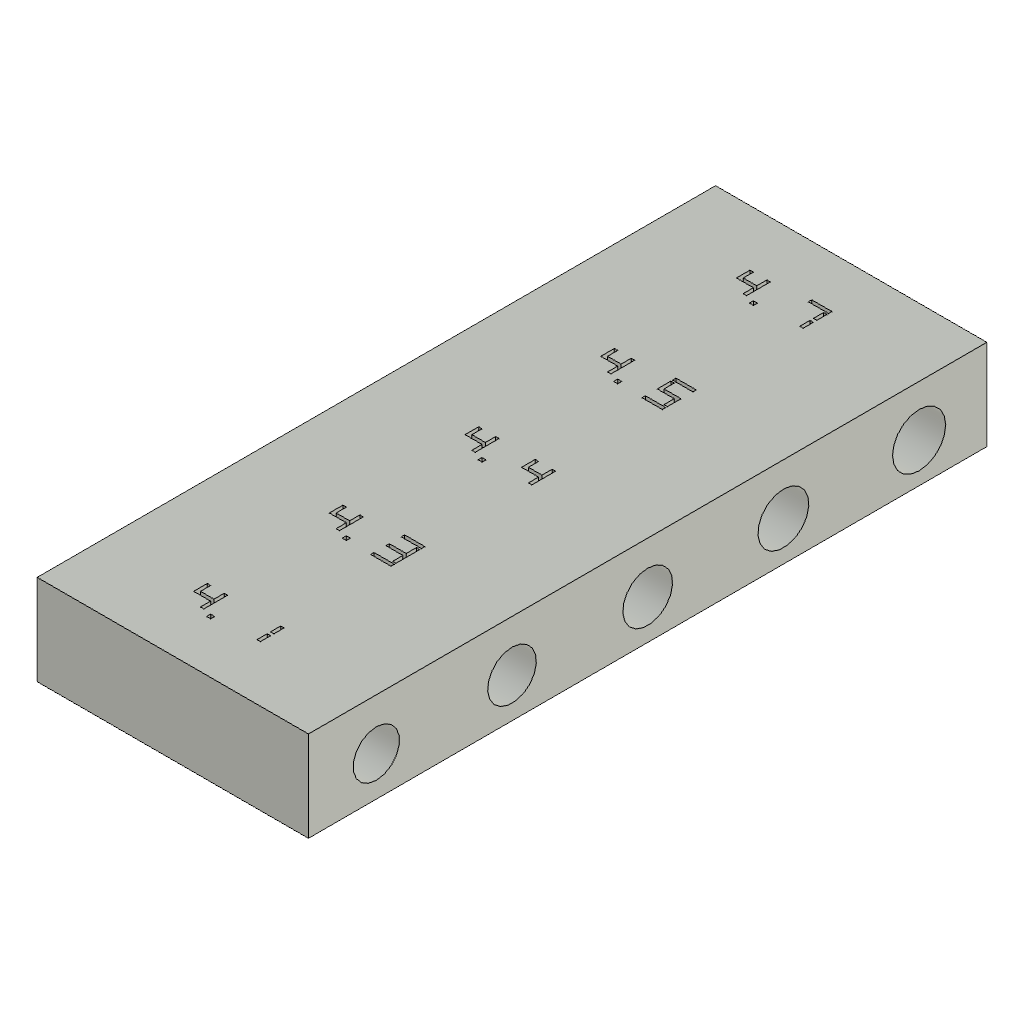
spar_fit_coupon (Autodesk Fusion 360 design; units mm, degrees)
part number: 2026-10-10-16-37-40-339
Autodesk Fusion 360 part; units mm, degrees
sketch "Fit block sketch" plane through (0, 0, 0) normal (0, 0, 1) x (1, 0, 0)
  line L0 (0, 0) -> (24, 0)
  line L1 (24, 0) -> (24, 60)
  line L2 (24, 60) -> (0, 60)
  line L3 (0, 60) -> (0, 0)
extrude "Fit block" add sketch "Fit block sketch" along normal blind 8
ref_plane "WorkPlane1" through (-0.05, 0, 0) normal (1, 0, 0) x (0, 1, 0)
sketch "Horizontal 4.1 mm fit bore sketch" plane through (-0.05, 0, 0) normal (1, 0, 0) x (0, 0, -1)
  circle A0 centre (-3.5, 6) radius 2.05
extrude "Horizontal 4.1 mm fit bore" cut sketch "Horizontal 4.1 mm fit bore sketch" along normal blind 24.1
ref_plane "WorkPlane2" through (0, 0, 7.4) normal (0, 0, 1) x (1, 0, 0)
sketch "Label 4.1 digit 0 f sketch" plane through (0, 0, 7.4) normal (0, 0, 1) x (1, 0, 0)
  line L0 (8, 6.15) -> (8.3, 6.15)
  line L1 (8.3, 6.15) -> (8.3, 7.05)
  line L2 (8.3, 7.05) -> (8, 7.05)
  line L3 (8, 7.05) -> (8, 6.15)
extrude "Label 4.1 digit 0 f" cut sketch "Label 4.1 digit 0 f sketch" along normal blind 1
ref_plane "WorkPlane3" through (0, 0, 7.4) normal (0, 0, 1) x (1, 0, 0)
sketch "Label 4.1 digit 0 g sketch" plane through (0, 0, 7.4) normal (0, 0, 1) x (1, 0, 0)
  line L0 (8, 5.85) -> (9.8, 5.85)
  line L1 (9.8, 5.85) -> (9.8, 6.15)
  line L2 (9.8, 6.15) -> (8, 6.15)
  line L3 (8, 6.15) -> (8, 5.85)
extrude "Label 4.1 digit 0 g" cut sketch "Label 4.1 digit 0 g sketch" along normal blind 1
ref_plane "WorkPlane4" through (0, 0, 7.4) normal (0, 0, 1) x (1, 0, 0)
sketch "Label 4.1 digit 0 b sketch" plane through (0, 0, 7.4) normal (0, 0, 1) x (1, 0, 0)
  line L0 (9.5, 6.15) -> (9.8, 6.15)
  line L1 (9.8, 6.15) -> (9.8, 7.05)
  line L2 (9.8, 7.05) -> (9.5, 7.05)
  line L3 (9.5, 7.05) -> (9.5, 6.15)
extrude "Label 4.1 digit 0 b" cut sketch "Label 4.1 digit 0 b sketch" along normal blind 1
ref_plane "WorkPlane5" through (0, 0, 7.4) normal (0, 0, 1) x (1, 0, 0)
sketch "Label 4.1 digit 0 c sketch" plane through (0, 0, 7.4) normal (0, 0, 1) x (1, 0, 0)
  line L0 (9.5, 4.95) -> (9.8, 4.95)
  line L1 (9.8, 4.95) -> (9.8, 5.85)
  line L2 (9.8, 5.85) -> (9.5, 5.85)
  line L3 (9.5, 5.85) -> (9.5, 4.95)
extrude "Label 4.1 digit 0 c" cut sketch "Label 4.1 digit 0 c sketch" along normal blind 1
ref_plane "WorkPlane6" through (0, 0, 7.4) normal (0, 0, 1) x (1, 0, 0)
sketch "Label 4.1 dot sketch" plane through (0, 0, 7.4) normal (0, 0, 1) x (1, 0, 0)
  line L0 (10.5, 4.5) -> (10.85, 4.5)
  line L1 (10.85, 4.5) -> (10.85, 4.85)
  line L2 (10.85, 4.85) -> (10.5, 4.85)
  line L3 (10.5, 4.85) -> (10.5, 4.5)
extrude "Label 4.1 dot" cut sketch "Label 4.1 dot sketch" along normal blind 1
ref_plane "WorkPlane7" through (0, 0, 7.4) normal (0, 0, 1) x (1, 0, 0)
sketch "Label 4.1 digit 2 b sketch" plane through (0, 0, 7.4) normal (0, 0, 1) x (1, 0, 0)
  line L0 (14.5, 6.15) -> (14.8, 6.15)
  line L1 (14.8, 6.15) -> (14.8, 7.05)
  line L2 (14.8, 7.05) -> (14.5, 7.05)
  line L3 (14.5, 7.05) -> (14.5, 6.15)
extrude "Label 4.1 digit 2 b" cut sketch "Label 4.1 digit 2 b sketch" along normal blind 1
ref_plane "WorkPlane8" through (0, 0, 7.4) normal (0, 0, 1) x (1, 0, 0)
sketch "Label 4.1 digit 2 c sketch" plane through (0, 0, 7.4) normal (0, 0, 1) x (1, 0, 0)
  line L0 (14.5, 4.95) -> (14.8, 4.95)
  line L1 (14.8, 4.95) -> (14.8, 5.85)
  line L2 (14.8, 5.85) -> (14.5, 5.85)
  line L3 (14.5, 5.85) -> (14.5, 4.95)
extrude "Label 4.1 digit 2 c" cut sketch "Label 4.1 digit 2 c sketch" along normal blind 1
ref_plane "WorkPlane9" through (-0.05, 0, 0) normal (1, 0, 0) x (0, 1, 0)
sketch "Horizontal 4.3 mm fit bore sketch" plane through (-0.05, 0, 0) normal (1, 0, 0) x (0, 0, -1)
  circle A0 centre (-3.5, 18) radius 2.15
extrude "Horizontal 4.3 mm fit bore" cut sketch "Horizontal 4.3 mm fit bore sketch" along normal blind 24.1
ref_plane "WorkPlane10" through (0, 0, 7.4) normal (0, 0, 1) x (1, 0, 0)
sketch "Label 4.3 digit 0 f sketch" plane through (0, 0, 7.4) normal (0, 0, 1) x (1, 0, 0)
  line L0 (8, 18.15) -> (8.3, 18.15)
  line L1 (8.3, 18.15) -> (8.3, 19.05)
  line L2 (8.3, 19.05) -> (8, 19.05)
  line L3 (8, 19.05) -> (8, 18.15)
extrude "Label 4.3 digit 0 f" cut sketch "Label 4.3 digit 0 f sketch" along normal blind 1
ref_plane "WorkPlane11" through (0, 0, 7.4) normal (0, 0, 1) x (1, 0, 0)
sketch "Label 4.3 digit 0 g sketch" plane through (0, 0, 7.4) normal (0, 0, 1) x (1, 0, 0)
  line L0 (8, 17.85) -> (9.8, 17.85)
  line L1 (9.8, 17.85) -> (9.8, 18.15)
  line L2 (9.8, 18.15) -> (8, 18.15)
  line L3 (8, 18.15) -> (8, 17.85)
extrude "Label 4.3 digit 0 g" cut sketch "Label 4.3 digit 0 g sketch" along normal blind 1
ref_plane "WorkPlane12" through (0, 0, 7.4) normal (0, 0, 1) x (1, 0, 0)
sketch "Label 4.3 digit 0 b sketch" plane through (0, 0, 7.4) normal (0, 0, 1) x (1, 0, 0)
  line L0 (9.5, 18.15) -> (9.8, 18.15)
  line L1 (9.8, 18.15) -> (9.8, 19.05)
  line L2 (9.8, 19.05) -> (9.5, 19.05)
  line L3 (9.5, 19.05) -> (9.5, 18.15)
extrude "Label 4.3 digit 0 b" cut sketch "Label 4.3 digit 0 b sketch" along normal blind 1
ref_plane "WorkPlane13" through (0, 0, 7.4) normal (0, 0, 1) x (1, 0, 0)
sketch "Label 4.3 digit 0 c sketch" plane through (0, 0, 7.4) normal (0, 0, 1) x (1, 0, 0)
  line L0 (9.5, 16.95) -> (9.8, 16.95)
  line L1 (9.8, 16.95) -> (9.8, 17.85)
  line L2 (9.8, 17.85) -> (9.5, 17.85)
  line L3 (9.5, 17.85) -> (9.5, 16.95)
extrude "Label 4.3 digit 0 c" cut sketch "Label 4.3 digit 0 c sketch" along normal blind 1
ref_plane "WorkPlane14" through (0, 0, 7.4) normal (0, 0, 1) x (1, 0, 0)
sketch "Label 4.3 dot sketch" plane through (0, 0, 7.4) normal (0, 0, 1) x (1, 0, 0)
  line L0 (10.5, 16.5) -> (10.85, 16.5)
  line L1 (10.85, 16.5) -> (10.85, 16.85)
  line L2 (10.85, 16.85) -> (10.5, 16.85)
  line L3 (10.5, 16.85) -> (10.5, 16.5)
extrude "Label 4.3 dot" cut sketch "Label 4.3 dot sketch" along normal blind 1
ref_plane "WorkPlane15" through (0, 0, 7.4) normal (0, 0, 1) x (1, 0, 0)
sketch "Label 4.3 digit 2 a sketch" plane through (0, 0, 7.4) normal (0, 0, 1) x (1, 0, 0)
  line L0 (13, 19.2) -> (14.8, 19.2)
  line L1 (14.8, 19.2) -> (14.8, 19.5)
  line L2 (14.8, 19.5) -> (13, 19.5)
  line L3 (13, 19.5) -> (13, 19.2)
extrude "Label 4.3 digit 2 a" cut sketch "Label 4.3 digit 2 a sketch" along normal blind 1
ref_plane "WorkPlane16" through (0, 0, 7.4) normal (0, 0, 1) x (1, 0, 0)
sketch "Label 4.3 digit 2 b sketch" plane through (0, 0, 7.4) normal (0, 0, 1) x (1, 0, 0)
  line L0 (14.5, 18.15) -> (14.8, 18.15)
  line L1 (14.8, 18.15) -> (14.8, 19.05)
  line L2 (14.8, 19.05) -> (14.5, 19.05)
  line L3 (14.5, 19.05) -> (14.5, 18.15)
extrude "Label 4.3 digit 2 b" cut sketch "Label 4.3 digit 2 b sketch" along normal blind 1
ref_plane "WorkPlane17" through (0, 0, 7.4) normal (0, 0, 1) x (1, 0, 0)
sketch "Label 4.3 digit 2 g sketch" plane through (0, 0, 7.4) normal (0, 0, 1) x (1, 0, 0)
  line L0 (13, 17.85) -> (14.8, 17.85)
  line L1 (14.8, 17.85) -> (14.8, 18.15)
  line L2 (14.8, 18.15) -> (13, 18.15)
  line L3 (13, 18.15) -> (13, 17.85)
extrude "Label 4.3 digit 2 g" cut sketch "Label 4.3 digit 2 g sketch" along normal blind 1
ref_plane "WorkPlane18" through (0, 0, 7.4) normal (0, 0, 1) x (1, 0, 0)
sketch "Label 4.3 digit 2 c sketch" plane through (0, 0, 7.4) normal (0, 0, 1) x (1, 0, 0)
  line L0 (14.5, 16.95) -> (14.8, 16.95)
  line L1 (14.8, 16.95) -> (14.8, 17.85)
  line L2 (14.8, 17.85) -> (14.5, 17.85)
  line L3 (14.5, 17.85) -> (14.5, 16.95)
extrude "Label 4.3 digit 2 c" cut sketch "Label 4.3 digit 2 c sketch" along normal blind 1
ref_plane "WorkPlane19" through (0, 0, 7.4) normal (0, 0, 1) x (1, 0, 0)
sketch "Label 4.3 digit 2 d sketch" plane through (0, 0, 7.4) normal (0, 0, 1) x (1, 0, 0)
  line L0 (13, 16.5) -> (14.8, 16.5)
  line L1 (14.8, 16.5) -> (14.8, 16.8)
  line L2 (14.8, 16.8) -> (13, 16.8)
  line L3 (13, 16.8) -> (13, 16.5)
extrude "Label 4.3 digit 2 d" cut sketch "Label 4.3 digit 2 d sketch" along normal blind 1
ref_plane "WorkPlane20" through (-0.05, 0, 0) normal (1, 0, 0) x (0, 1, 0)
sketch "Horizontal 4.4 mm fit bore sketch" plane through (-0.05, 0, 0) normal (1, 0, 0) x (0, 0, -1)
  circle A0 centre (-3.5, 30) radius 2.2
extrude "Horizontal 4.4 mm fit bore" cut sketch "Horizontal 4.4 mm fit bore sketch" along normal blind 24.1
ref_plane "WorkPlane21" through (0, 0, 7.4) normal (0, 0, 1) x (1, 0, 0)
sketch "Label 4.4 digit 0 f sketch" plane through (0, 0, 7.4) normal (0, 0, 1) x (1, 0, 0)
  line L0 (8, 30.15) -> (8.3, 30.15)
  line L1 (8.3, 30.15) -> (8.3, 31.05)
  line L2 (8.3, 31.05) -> (8, 31.05)
  line L3 (8, 31.05) -> (8, 30.15)
extrude "Label 4.4 digit 0 f" cut sketch "Label 4.4 digit 0 f sketch" along normal blind 1
ref_plane "WorkPlane22" through (0, 0, 7.4) normal (0, 0, 1) x (1, 0, 0)
sketch "Label 4.4 digit 0 g sketch" plane through (0, 0, 7.4) normal (0, 0, 1) x (1, 0, 0)
  line L0 (8, 29.85) -> (9.8, 29.85)
  line L1 (9.8, 29.85) -> (9.8, 30.15)
  line L2 (9.8, 30.15) -> (8, 30.15)
  line L3 (8, 30.15) -> (8, 29.85)
extrude "Label 4.4 digit 0 g" cut sketch "Label 4.4 digit 0 g sketch" along normal blind 1
ref_plane "WorkPlane23" through (0, 0, 7.4) normal (0, 0, 1) x (1, 0, 0)
sketch "Label 4.4 digit 0 b sketch" plane through (0, 0, 7.4) normal (0, 0, 1) x (1, 0, 0)
  line L0 (9.5, 30.15) -> (9.8, 30.15)
  line L1 (9.8, 30.15) -> (9.8, 31.05)
  line L2 (9.8, 31.05) -> (9.5, 31.05)
  line L3 (9.5, 31.05) -> (9.5, 30.15)
extrude "Label 4.4 digit 0 b" cut sketch "Label 4.4 digit 0 b sketch" along normal blind 1
ref_plane "WorkPlane24" through (0, 0, 7.4) normal (0, 0, 1) x (1, 0, 0)
sketch "Label 4.4 digit 0 c sketch" plane through (0, 0, 7.4) normal (0, 0, 1) x (1, 0, 0)
  line L0 (9.5, 28.95) -> (9.8, 28.95)
  line L1 (9.8, 28.95) -> (9.8, 29.85)
  line L2 (9.8, 29.85) -> (9.5, 29.85)
  line L3 (9.5, 29.85) -> (9.5, 28.95)
extrude "Label 4.4 digit 0 c" cut sketch "Label 4.4 digit 0 c sketch" along normal blind 1
ref_plane "WorkPlane25" through (0, 0, 7.4) normal (0, 0, 1) x (1, 0, 0)
sketch "Label 4.4 dot sketch" plane through (0, 0, 7.4) normal (0, 0, 1) x (1, 0, 0)
  line L0 (10.5, 28.5) -> (10.85, 28.5)
  line L1 (10.85, 28.5) -> (10.85, 28.85)
  line L2 (10.85, 28.85) -> (10.5, 28.85)
  line L3 (10.5, 28.85) -> (10.5, 28.5)
extrude "Label 4.4 dot" cut sketch "Label 4.4 dot sketch" along normal blind 1
ref_plane "WorkPlane26" through (0, 0, 7.4) normal (0, 0, 1) x (1, 0, 0)
sketch "Label 4.4 digit 2 f sketch" plane through (0, 0, 7.4) normal (0, 0, 1) x (1, 0, 0)
  line L0 (13, 30.15) -> (13.3, 30.15)
  line L1 (13.3, 30.15) -> (13.3, 31.05)
  line L2 (13.3, 31.05) -> (13, 31.05)
  line L3 (13, 31.05) -> (13, 30.15)
extrude "Label 4.4 digit 2 f" cut sketch "Label 4.4 digit 2 f sketch" along normal blind 1
ref_plane "WorkPlane27" through (0, 0, 7.4) normal (0, 0, 1) x (1, 0, 0)
sketch "Label 4.4 digit 2 g sketch" plane through (0, 0, 7.4) normal (0, 0, 1) x (1, 0, 0)
  line L0 (13, 29.85) -> (14.8, 29.85)
  line L1 (14.8, 29.85) -> (14.8, 30.15)
  line L2 (14.8, 30.15) -> (13, 30.15)
  line L3 (13, 30.15) -> (13, 29.85)
extrude "Label 4.4 digit 2 g" cut sketch "Label 4.4 digit 2 g sketch" along normal blind 1
ref_plane "WorkPlane28" through (0, 0, 7.4) normal (0, 0, 1) x (1, 0, 0)
sketch "Label 4.4 digit 2 b sketch" plane through (0, 0, 7.4) normal (0, 0, 1) x (1, 0, 0)
  line L0 (14.5, 30.15) -> (14.8, 30.15)
  line L1 (14.8, 30.15) -> (14.8, 31.05)
  line L2 (14.8, 31.05) -> (14.5, 31.05)
  line L3 (14.5, 31.05) -> (14.5, 30.15)
extrude "Label 4.4 digit 2 b" cut sketch "Label 4.4 digit 2 b sketch" along normal blind 1
ref_plane "WorkPlane29" through (0, 0, 7.4) normal (0, 0, 1) x (1, 0, 0)
sketch "Label 4.4 digit 2 c sketch" plane through (0, 0, 7.4) normal (0, 0, 1) x (1, 0, 0)
  line L0 (14.5, 28.95) -> (14.8, 28.95)
  line L1 (14.8, 28.95) -> (14.8, 29.85)
  line L2 (14.8, 29.85) -> (14.5, 29.85)
  line L3 (14.5, 29.85) -> (14.5, 28.95)
extrude "Label 4.4 digit 2 c" cut sketch "Label 4.4 digit 2 c sketch" along normal blind 1
ref_plane "WorkPlane30" through (-0.05, 0, 0) normal (1, 0, 0) x (0, 1, 0)
sketch "Horizontal 4.5 mm fit bore sketch" plane through (-0.05, 0, 0) normal (1, 0, 0) x (0, 0, -1)
  circle A0 centre (-3.5, 42) radius 2.25
extrude "Horizontal 4.5 mm fit bore" cut sketch "Horizontal 4.5 mm fit bore sketch" along normal blind 24.1
ref_plane "WorkPlane31" through (0, 0, 7.4) normal (0, 0, 1) x (1, 0, 0)
sketch "Label 4.5 digit 0 f sketch" plane through (0, 0, 7.4) normal (0, 0, 1) x (1, 0, 0)
  line L0 (8, 42.15) -> (8.3, 42.15)
  line L1 (8.3, 42.15) -> (8.3, 43.05)
  line L2 (8.3, 43.05) -> (8, 43.05)
  line L3 (8, 43.05) -> (8, 42.15)
extrude "Label 4.5 digit 0 f" cut sketch "Label 4.5 digit 0 f sketch" along normal blind 1
ref_plane "WorkPlane32" through (0, 0, 7.4) normal (0, 0, 1) x (1, 0, 0)
sketch "Label 4.5 digit 0 g sketch" plane through (0, 0, 7.4) normal (0, 0, 1) x (1, 0, 0)
  line L0 (8, 41.85) -> (9.8, 41.85)
  line L1 (9.8, 41.85) -> (9.8, 42.15)
  line L2 (9.8, 42.15) -> (8, 42.15)
  line L3 (8, 42.15) -> (8, 41.85)
extrude "Label 4.5 digit 0 g" cut sketch "Label 4.5 digit 0 g sketch" along normal blind 1
ref_plane "WorkPlane33" through (0, 0, 7.4) normal (0, 0, 1) x (1, 0, 0)
sketch "Label 4.5 digit 0 b sketch" plane through (0, 0, 7.4) normal (0, 0, 1) x (1, 0, 0)
  line L0 (9.5, 42.15) -> (9.8, 42.15)
  line L1 (9.8, 42.15) -> (9.8, 43.05)
  line L2 (9.8, 43.05) -> (9.5, 43.05)
  line L3 (9.5, 43.05) -> (9.5, 42.15)
extrude "Label 4.5 digit 0 b" cut sketch "Label 4.5 digit 0 b sketch" along normal blind 1
ref_plane "WorkPlane34" through (0, 0, 7.4) normal (0, 0, 1) x (1, 0, 0)
sketch "Label 4.5 digit 0 c sketch" plane through (0, 0, 7.4) normal (0, 0, 1) x (1, 0, 0)
  line L0 (9.5, 40.95) -> (9.8, 40.95)
  line L1 (9.8, 40.95) -> (9.8, 41.85)
  line L2 (9.8, 41.85) -> (9.5, 41.85)
  line L3 (9.5, 41.85) -> (9.5, 40.95)
extrude "Label 4.5 digit 0 c" cut sketch "Label 4.5 digit 0 c sketch" along normal blind 1
ref_plane "WorkPlane35" through (0, 0, 7.4) normal (0, 0, 1) x (1, 0, 0)
sketch "Label 4.5 dot sketch" plane through (0, 0, 7.4) normal (0, 0, 1) x (1, 0, 0)
  line L0 (10.5, 40.5) -> (10.85, 40.5)
  line L1 (10.85, 40.5) -> (10.85, 40.85)
  line L2 (10.85, 40.85) -> (10.5, 40.85)
  line L3 (10.5, 40.85) -> (10.5, 40.5)
extrude "Label 4.5 dot" cut sketch "Label 4.5 dot sketch" along normal blind 1
ref_plane "WorkPlane36" through (0, 0, 7.4) normal (0, 0, 1) x (1, 0, 0)
sketch "Label 4.5 digit 2 a sketch" plane through (0, 0, 7.4) normal (0, 0, 1) x (1, 0, 0)
  line L0 (13, 43.2) -> (14.8, 43.2)
  line L1 (14.8, 43.2) -> (14.8, 43.5)
  line L2 (14.8, 43.5) -> (13, 43.5)
  line L3 (13, 43.5) -> (13, 43.2)
extrude "Label 4.5 digit 2 a" cut sketch "Label 4.5 digit 2 a sketch" along normal blind 1
ref_plane "WorkPlane37" through (0, 0, 7.4) normal (0, 0, 1) x (1, 0, 0)
sketch "Label 4.5 digit 2 f sketch" plane through (0, 0, 7.4) normal (0, 0, 1) x (1, 0, 0)
  line L0 (13, 42.15) -> (13.3, 42.15)
  line L1 (13.3, 42.15) -> (13.3, 43.05)
  line L2 (13.3, 43.05) -> (13, 43.05)
  line L3 (13, 43.05) -> (13, 42.15)
extrude "Label 4.5 digit 2 f" cut sketch "Label 4.5 digit 2 f sketch" along normal blind 1
ref_plane "WorkPlane38" through (0, 0, 7.4) normal (0, 0, 1) x (1, 0, 0)
sketch "Label 4.5 digit 2 g sketch" plane through (0, 0, 7.4) normal (0, 0, 1) x (1, 0, 0)
  line L0 (13, 41.85) -> (14.8, 41.85)
  line L1 (14.8, 41.85) -> (14.8, 42.15)
  line L2 (14.8, 42.15) -> (13, 42.15)
  line L3 (13, 42.15) -> (13, 41.85)
extrude "Label 4.5 digit 2 g" cut sketch "Label 4.5 digit 2 g sketch" along normal blind 1
ref_plane "WorkPlane39" through (0, 0, 7.4) normal (0, 0, 1) x (1, 0, 0)
sketch "Label 4.5 digit 2 c sketch" plane through (0, 0, 7.4) normal (0, 0, 1) x (1, 0, 0)
  line L0 (14.5, 40.95) -> (14.8, 40.95)
  line L1 (14.8, 40.95) -> (14.8, 41.85)
  line L2 (14.8, 41.85) -> (14.5, 41.85)
  line L3 (14.5, 41.85) -> (14.5, 40.95)
extrude "Label 4.5 digit 2 c" cut sketch "Label 4.5 digit 2 c sketch" along normal blind 1
ref_plane "WorkPlane40" through (0, 0, 7.4) normal (0, 0, 1) x (1, 0, 0)
sketch "Label 4.5 digit 2 d sketch" plane through (0, 0, 7.4) normal (0, 0, 1) x (1, 0, 0)
  line L0 (13, 40.5) -> (14.8, 40.5)
  line L1 (14.8, 40.5) -> (14.8, 40.8)
  line L2 (14.8, 40.8) -> (13, 40.8)
  line L3 (13, 40.8) -> (13, 40.5)
extrude "Label 4.5 digit 2 d" cut sketch "Label 4.5 digit 2 d sketch" along normal blind 1
ref_plane "WorkPlane41" through (-0.05, 0, 0) normal (1, 0, 0) x (0, 1, 0)
sketch "Horizontal 4.7 mm fit bore sketch" plane through (-0.05, 0, 0) normal (1, 0, 0) x (0, 0, -1)
  circle A0 centre (-3.5, 54) radius 2.35
extrude "Horizontal 4.7 mm fit bore" cut sketch "Horizontal 4.7 mm fit bore sketch" along normal blind 24.1
ref_plane "WorkPlane42" through (0, 0, 7.4) normal (0, 0, 1) x (1, 0, 0)
sketch "Label 4.7 digit 0 f sketch" plane through (0, 0, 7.4) normal (0, 0, 1) x (1, 0, 0)
  line L0 (8, 54.15) -> (8.3, 54.15)
  line L1 (8.3, 54.15) -> (8.3, 55.05)
  line L2 (8.3, 55.05) -> (8, 55.05)
  line L3 (8, 55.05) -> (8, 54.15)
extrude "Label 4.7 digit 0 f" cut sketch "Label 4.7 digit 0 f sketch" along normal blind 1
ref_plane "WorkPlane43" through (0, 0, 7.4) normal (0, 0, 1) x (1, 0, 0)
sketch "Label 4.7 digit 0 g sketch" plane through (0, 0, 7.4) normal (0, 0, 1) x (1, 0, 0)
  line L0 (8, 53.85) -> (9.8, 53.85)
  line L1 (9.8, 53.85) -> (9.8, 54.15)
  line L2 (9.8, 54.15) -> (8, 54.15)
  line L3 (8, 54.15) -> (8, 53.85)
extrude "Label 4.7 digit 0 g" cut sketch "Label 4.7 digit 0 g sketch" along normal blind 1
ref_plane "WorkPlane44" through (0, 0, 7.4) normal (0, 0, 1) x (1, 0, 0)
sketch "Label 4.7 digit 0 b sketch" plane through (0, 0, 7.4) normal (0, 0, 1) x (1, 0, 0)
  line L0 (9.5, 54.15) -> (9.8, 54.15)
  line L1 (9.8, 54.15) -> (9.8, 55.05)
  line L2 (9.8, 55.05) -> (9.5, 55.05)
  line L3 (9.5, 55.05) -> (9.5, 54.15)
extrude "Label 4.7 digit 0 b" cut sketch "Label 4.7 digit 0 b sketch" along normal blind 1
ref_plane "WorkPlane45" through (0, 0, 7.4) normal (0, 0, 1) x (1, 0, 0)
sketch "Label 4.7 digit 0 c sketch" plane through (0, 0, 7.4) normal (0, 0, 1) x (1, 0, 0)
  line L0 (9.5, 52.95) -> (9.8, 52.95)
  line L1 (9.8, 52.95) -> (9.8, 53.85)
  line L2 (9.8, 53.85) -> (9.5, 53.85)
  line L3 (9.5, 53.85) -> (9.5, 52.95)
extrude "Label 4.7 digit 0 c" cut sketch "Label 4.7 digit 0 c sketch" along normal blind 1
ref_plane "WorkPlane46" through (0, 0, 7.4) normal (0, 0, 1) x (1, 0, 0)
sketch "Label 4.7 dot sketch" plane through (0, 0, 7.4) normal (0, 0, 1) x (1, 0, 0)
  line L0 (10.5, 52.5) -> (10.85, 52.5)
  line L1 (10.85, 52.5) -> (10.85, 52.85)
  line L2 (10.85, 52.85) -> (10.5, 52.85)
  line L3 (10.5, 52.85) -> (10.5, 52.5)
extrude "Label 4.7 dot" cut sketch "Label 4.7 dot sketch" along normal blind 1
ref_plane "WorkPlane47" through (0, 0, 7.4) normal (0, 0, 1) x (1, 0, 0)
sketch "Label 4.7 digit 2 a sketch" plane through (0, 0, 7.4) normal (0, 0, 1) x (1, 0, 0)
  line L0 (13, 55.2) -> (14.8, 55.2)
  line L1 (14.8, 55.2) -> (14.8, 55.5)
  line L2 (14.8, 55.5) -> (13, 55.5)
  line L3 (13, 55.5) -> (13, 55.2)
extrude "Label 4.7 digit 2 a" cut sketch "Label 4.7 digit 2 a sketch" along normal blind 1
ref_plane "WorkPlane48" through (0, 0, 7.4) normal (0, 0, 1) x (1, 0, 0)
sketch "Label 4.7 digit 2 b sketch" plane through (0, 0, 7.4) normal (0, 0, 1) x (1, 0, 0)
  line L0 (14.5, 54.15) -> (14.8, 54.15)
  line L1 (14.8, 54.15) -> (14.8, 55.05)
  line L2 (14.8, 55.05) -> (14.5, 55.05)
  line L3 (14.5, 55.05) -> (14.5, 54.15)
extrude "Label 4.7 digit 2 b" cut sketch "Label 4.7 digit 2 b sketch" along normal blind 1
ref_plane "WorkPlane49" through (0, 0, 7.4) normal (0, 0, 1) x (1, 0, 0)
sketch "Label 4.7 digit 2 c sketch" plane through (0, 0, 7.4) normal (0, 0, 1) x (1, 0, 0)
  line L0 (14.5, 52.95) -> (14.8, 52.95)
  line L1 (14.8, 52.95) -> (14.8, 53.85)
  line L2 (14.8, 53.85) -> (14.5, 53.85)
  line L3 (14.5, 53.85) -> (14.5, 52.95)
extrude "Label 4.7 digit 2 c" cut sketch "Label 4.7 digit 2 c sketch" along normal blind 1
named bodies: "spar_fit_coupon - printable solid"
